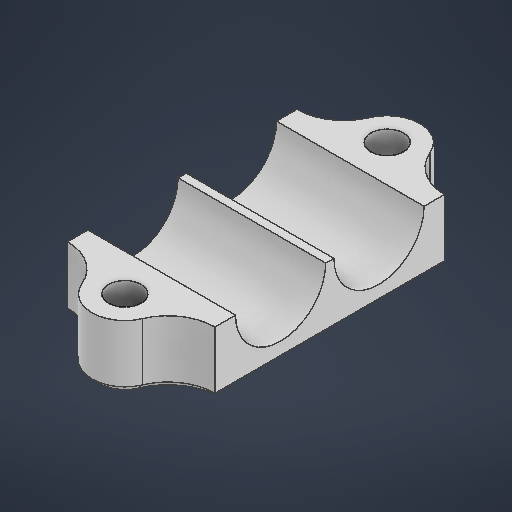
# Autodesk Inventor part: Substrate_DC jack hoder
Saved by Autodesk Inventor 2026.2 (Build 302298010, 298A)
## iProperties
Created: 2026-04-28
Part Number: Substrate_DC jack hoder
Material: 일반
Document SubType Name: Modeling
Designer: work
Density: 1 g/cm^3
Appearance: 기본값
Author: work
Autodesk Inventor part; units mm, degrees
ref_plane "YZ Plane" through (0, 0, 0) normal (1, 0, 0) x (0, 1, 0)
ref_plane "XZ Plane" through (0, 0, 0) normal (0, 1, 0) x (-1, 0, 0)
ref_plane "XY Plane" through (0, 0, 0) normal (0, 0, 1) x (1, 0, 0)
sketch "스케치1" plane through (0, 0, 0) normal (1, 0, 0) x (0, 1, 0)
  circle A0 centre (0, 0) radius 5.5
  line L0 (0, 0) -> (0, -12)
  circle A1 centre (0, -12) radius 5.5
  line L1 (0, -12) -> (0, -20)
  line L2 (0, -20) -> (-8, -20)
  line L3 (-8, -20) -> (-8, 8)
  line L4 (-8, 8) -> (0, 8)
  line L5 (0, 8) -> (0, 0)
  point P0 (0, -17.5)
  point P1 (0, -6.5)
  point P2 (0, -5.5)
  point P3 (0, 5.5)
  dimension "d0" = 11
  dimension "d1" = 12
  dimension "d2" = 11
  dimension "d3" = 8
  dimension "d4" = 8
  dimension "d5" = 8
  constraints: 12 end point, 3 perpendicular, 2 centre point, 2 coincident, 2 vertical, 1 horizontal
  measures "d0" diameter of A0
  measures "d1" distance of L0.start L0.end
  measures "d2" diameter of A1
  measures "d3" distance of L1.start L1.end
  measures "d4" distance of L4.end L0.start
  measures "d5" distance between parallel lines of L3 L5
extrude "돌출1" add sketch "스케치1" along normal blind 18 contours A0 L0 A1 L1 L2 L3 L4 L5
sketch "스케치2" plane through (0, 0, -17.5) normal (0, 1, 0) x (1, 0, 0)
  line L0 (0, 2.5) -> (0, 0) projected
  line L1 (0, 0) -> (18, 0) projected
  line L2 (18, 2.5) -> (18, 0) projected
  line L3 (0, 2.5) -> (18, 2.5) construction
  line L4 (0, -23) -> (18, -23) projected
  line L5 (0, -25.5) -> (18, -25.5) projected
  line L6 (0, -11) -> (0, -12) projected
  line L7 (0, -12) -> (18, -12) construction
  line L8 (18, -11) -> (18, -12) projected
  line L9 (0, -11) -> (18, -11) construction
  line L10 (9, 2.5) -> (9, -25.5) construction
  circle A0 centre (9, 4.5) radius 2
  circle A1 centre (9, 4.5) radius 4
  arc A2 (0, 2.5) -> (5.3077, 6.0385) centre (0, 8.25) ccw
  line L11 (0, 2.5) -> (18, 2.5) projected
  arc A3 (12.6923, 6.0385) -> (18, 2.5) centre (18, 8.25) ccw
  line L12 (18, -11.5) -> (0, -11.5) construction
  circle A4 centre (9, -27.5) radius 2
  circle A5 centre (9, -27.5) radius 4
  arc A6 (5.3077, -29.0385) -> (0, -25.5) centre (0, -31.25) ccw
  arc A7 (18, -25.5) -> (12.6923, -29.0385) centre (18, -31.25) ccw
  line L13 (9, -27.5) -> (9, 4.5) construction
  point P0 (0, -17.5)
  point P1 (9, -11.5)
  point P2 (9, 2.5)
  point P3 (12.6923, 6.0385)
  point P4 (9, -25.5)
  dimension "d9" = 8
  dimension "d8" = 4
  dimension "d10" = 32
  constraints: 8 point on circle, 8 symmetric about line, 6 centre point, 6 end point, 6 midpoint, 2 coincident, 1 horizontal, 1 tangent, 1 vertical, 11 other
  measures "d8" diameter of A0
  measures "d10" distance of A0.centre A4.centre
extrude "돌출2" add sketch "스케치2" against normal up to surface (8 mm away) contours A2 A1 L11 | A1 L11 | A3 L11 A1 | L5 A5 A6 | L5 A5 | L5 A7 A5 picked at (6.0814, 6.0662) picked at (6.0814, -29.0662)
chamfer "모따기1" distance 1 angle 45 8 edges at (14.8105, -8, 8.9657) (9, -8, 14) (3.1895, -8, 8.9657) (18, -8, -6) (0, -8, -6) (3.1895, -8, -20.9657) (9, -8, -26) (14.8105, -8, -20.9657)
